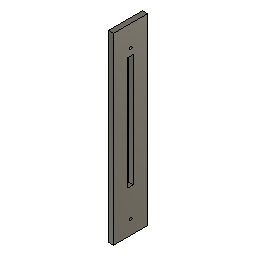
REGULABLE (Autodesk Fusion 360 design; units mm, degrees)
part number: 2026-06-03-16-49-12-071
Autodesk Fusion 360 part; units mm, degrees
sketch "Sketch1" plane through (0, 0, 0) normal (1, 0, 0) x (0, 1, 0)
  line L0 (0, 0) -> (120, 0)
  line L1 (120, 0) -> (120, 650)
  line L2 (120, 650) -> (0, 650)
  line L3 (0, 650) -> (0, 0)
  line L4 (70, 550) -> (51, 550)
  line L5 (51, 550) -> (51, 150)
  line L6 (51, 150) -> (70, 150)
  line L7 (70, 150) -> (70, 550)
  line L8 (70, 550) -> (51, 150) construction
  line L9 (51, 550) -> (70, 150) construction
  circle A0 centre (60.4487, 575) radius 5
  circle A1 centre (60.6683, 50) radius 5
  line L10 (60.5, 1150.0061) -> (60.5, 149.9939) construction
  line L11 (464.899, 350) -> (-224.899, 350) construction
  arc A2 (60.5, 149.9939) -> (60.6683, 50) centre (29761.3588, 149.9939) ccw construction
  point P0 (60.5, 350)
  point P1 (60.5, 650)
  point P2 (0, 256.6634)
  point P3 (120, 350)
  dimension "d1" = 400
  dimension "d2" = 19
  dimension "d3" = 10
  dimension "d4" = 10
  dimension "d6" = 75
  dimension "d9" = 120
  dimension "d10" = 650
  dimension "d11" = 100
  dimension "d12" = 150
  dimension "d13" = 50
  dimension "d14" = 100
  constraint horizontal L0
  constraint vertical L1
  constraint horizontal L2
  constraint vertical L3
  constraint coincident L0.start L3.end
  constraint horizontal L4
  constraint perpendicular L4 L5
  constraint parallel L4 L6
  constraint parallel L5 L7
  constraint coincident L8 P0
  constraint coincident L9 P0
  constraint midpoint L10 P1
  constraint coincident L2 P1
  constraint perpendicular L6 L10
  constraint coincident L3 P2
  constraint coincident P0 L10
  constraint midpoint L11 P3
  constraint coincident L1 P3
  constraint perpendicular L5 L11
  constraint coincident P0 L11
  constraint coincident A1.centre A2.end
  constraint tangent L10 A2
  measures "d1" distance of L4.end L5.end
  measures "d2" distance of L5.end L6.end
  measures "d3" diameter of A0
  measures "d4" diameter of A1
  measures "d6" distance of L2 A0.centre
  measures "d9" distance of L0.start L0.end
  measures "d10" distance of L0.start L2.end
  measures "d11" distance of L2 L4
  measures "d12" distance of L0 L6
  measures "d13" distance of L1 L4.start
  measures "d14" distance of L6 A1.centre
extrude "Extrude1" add sketch "Sketch1" along normal blind 18
